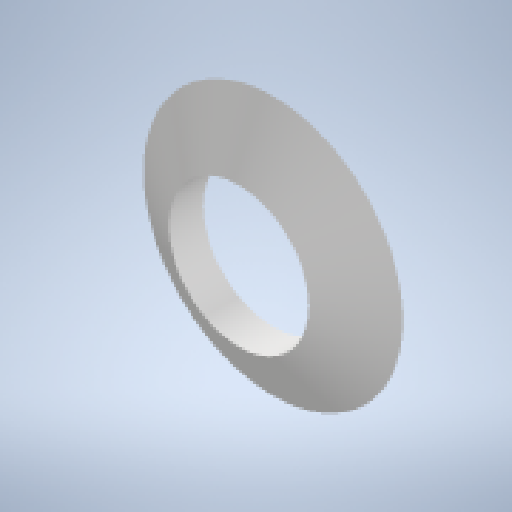
# Autodesk Inventor part: вокруг камеры 1
Saved by Autodesk Inventor 2024.2 (Build 282272000, 272)
## iProperties
Created: 2026-11-06
Part Number: вокруг камеры 1
Material: Типовые
Document SubType Name: Modeling
Designer: katya_notebook
Density: 1 g/cm^3
Appearance: По умолчанию
Author: katya_notebook
Autodesk Inventor part; units mm, degrees
ref_plane "YZ Plane" through (0, 0, 0) normal (1, 0, 0) x (0, 1, 0)
ref_plane "XZ Plane" through (0, 0, 0) normal (0, 1, 0) x (-1, 0, 0)
ref_plane "XY Plane" through (0, 0, 0) normal (0, 0, 1) x (1, 0, 0)
sketch "Эскиз2" plane through (0, 0, 0) normal (0, 1, 0) x (-1, 0, 0)
  line L0 (-8, 0) -> (8, 0) projected
  line L1 (0, 0) -> (0, 19.4532) construction
  line L2 (0, 0) -> (-14.8304, 0)
  line L3 (-14.8304, 0) -> (-14.8304, 4)
  line L4 (-14.8304, 4) -> (0, 4)
  line L5 (0, 4) -> (0, 0)
  line L6 (-14.8304, 0) -> (-7.9022, 4)
  line L7 (-8, 0) -> (8, 0) projected
  line L8 (-8, 4) -> (-8, 0)
  point P0 (-8, 2)
  point P1 (-8, 3.9435)
  dimension "d0" = 4
  dimension "d1" = 60
  dimension "d3" = 8
  constraints: 14 end point, 3 point on line, 2 parallel, 2 vertical, 1 horizontal, 1 midpoint, 1 perpendicular
  measures "d0" distance of L2.end L3.end
  measures "d1" angle of L3 L6
  measures "d3" distance from line of point (-8, 2) L1
revolve "Вращение1" add sketch "Эскиз2" angle 360 about axis through (0, 0, 0) along (0, 0, 1) contours L2 L6 L8
